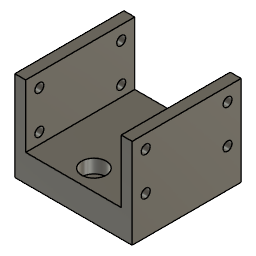
BallCameraHolder_Horizontal_RC2_short_base10mm (Autodesk Fusion 360 design; units mm, degrees)
part number: 2026-10-22-13-06-07-464
Autodesk Fusion 360 part; units mm, degrees
sketch "Sketch2" plane through (0, 0, 0) normal (0, 0, 1) x (1, 0, 0)
  line L0 (-21.5, 20) -> (21.5, 20)
  line L1 (21.5, 20) -> (21.5, -20)
  line L2 (21.5, -20) -> (-21.5, -20)
  line L3 (-21.5, -20) -> (-21.5, 20)
  line L4 (-21.5, 20) -> (21.5, -20) construction
  line L5 (21.5, 20) -> (-21.5, -20) construction
  line L6 (0, -20) -> (0, -12.5) construction
  circle A0 centre (0, -12.5) radius 2
  line L7 (0, 20) -> (0, 12.5) construction
  circle A1 centre (0, 12.5) radius 2
  dimension "d1" = 43
  dimension "d2" = 40
  dimension "d3" = 7.5
  dimension "d4" = 4
  dimension "d5" = 7.5
  dimension "d6" = 4
  constraint horizontal L0
  constraint perpendicular L0 L1
  constraint parallel L0 L2
  constraint parallel L1 L3
  constraint coincident L4 origin
  constraint coincident L5 origin
  constraint midpoint L2 L6.start
  constraint perpendicular L2 L6
  constraint coincident L6.end A0.centre
  constraint midpoint L0 L7.start
  constraint perpendicular L0 L7
  constraint coincident L7.end A1.centre
  measures "d1" distance of L1.end L2.end
  measures "d2" distance of L0.end L1.end
  measures "d3" distance of L6.start L6.end
  measures "d4" diameter of A0
  measures "d5" distance of L7.start L7.end
  measures "d6" diameter of A1
extrude "Extrude1" add sketch "Sketch2" along normal blind 5
sketch "Sketch3" plane through (0, 0, 5) normal (0, 0, 1) x (-1, 0, 0)
  circle A0 centre (0, 12.5) radius 2
  circle A1 centre (0, -12.5) radius 2
  line L0 (21.5, 20) -> (-21.5, 20)
  line L1 (-21.5, 20) -> (-21.5, -20)
  line L2 (-21.5, -20) -> (21.5, -20)
  line L3 (21.5, -20) -> (21.5, 20)
  line L4 (21.5, 20) -> (17.5, 20)
  line L5 (17.5, 20) -> (17.5, -20)
  line L6 (17.5, -20) -> (21.5, -20)
  line L7 (21.5, -20) -> (21.5, 20)
  line L8 (-21.5, -20) -> (-17.5, -20)
  line L9 (-17.5, -20) -> (-17.5, 20)
  line L10 (-17.5, 20) -> (-21.5, 20)
  line L11 (-21.5, 20) -> (-21.5, -20)
  circle A2 centre (0, 12.5) radius 4.5
  circle A3 centre (0, -12.5) radius 4.5
  dimension "d9" = 4
  dimension "d10" = 4
  dimension "d11" = 9
  dimension "d12" = 9
  constraint horizontal L4
  constraint vertical L5
  constraint horizontal L6
  constraint vertical L7
  constraint coincident L0.start L3.end
  constraint horizontal L8
  constraint vertical L9
  constraint horizontal L10
  constraint vertical L11
  constraint coincident L1.end L2.start
  constraint concentric A0 A2
  constraint concentric A1 A3
  measures "d9" distance of L0.start L4.end
  measures "d10" distance of L1.end L8.end
  measures "d11" diameter of A2
  measures "d12" diameter of A3
extrude "Extrude2" add sketch "Sketch3" along normal blind 28 contours L0 L2 L3 L4 L5 L6 L7 | L0 L1 L2 L8 L9 L10 L11
extrude "Extrude3" add sketch "Sketch3" along normal blind 5 contours L0 L2 L5 L9
sketch "Sketch4" plane through (21.5, 0, 0) normal (1, 0, 0) x (0, 1, 0)
  line L0 (20, 0) -> (20, 33)
  line L1 (20, 33) -> (-20, 33)
  line L2 (-20, 33) -> (-20, 0)
  line L3 (-20, 33) -> (-15, 33) construction
  line L4 (-15, 33) -> (-15, 28) construction
  line L5 (-15, 28) -> (-20, 28) construction
  line L6 (-20, 28) -> (-20, 33) construction
  line L7 (20, 33) -> (15, 33) construction
  line L8 (15, 33) -> (15, 28) construction
  line L9 (15, 28) -> (20, 28) construction
  line L10 (20, 28) -> (20, 33) construction
  line L11 (-20, 33) -> (-20, 10) construction
  line L12 (-20, 10) -> (-15, 10) construction
  line L13 (-15, 10) -> (-15, 14) construction
  line L14 (-15, 14) -> (-20, 14) construction
  line L15 (-20, 14) -> (-20, 10) construction
  line L16 (20, 33) -> (20, 10) construction
  line L17 (20, 10) -> (15, 10) construction
  line L18 (15, 10) -> (15, 14) construction
  line L19 (15, 14) -> (20, 14) construction
  line L20 (20, 14) -> (20, 10) construction
  circle A0 centre (-15, 14) radius 1.65
  circle A1 centre (15, 14) radius 1.65
  circle A2 centre (-15, 28) radius 1.65
  circle A3 centre (15, 28) radius 1.65
  dimension "d17" = 5
  dimension "d18" = 5
  dimension "d22" = 5
  dimension "d23" = 5
  dimension "d29" = 23
  dimension "d30" = 5
  dimension "d31" = 4
  dimension "d32" = 23
  dimension "d33" = 5
  dimension "d34" = 4
  dimension "d35" = 3.3
  dimension "d36" = 3.3
  dimension "d37" = 3.3
  dimension "d38" = 3.3
  constraint horizontal L3
  constraint vertical L4
  constraint horizontal L5
  constraint vertical L6
  constraint coincident L1.end L2.start
  constraint horizontal L7
  constraint vertical L8
  constraint horizontal L9
  constraint vertical L10
  constraint coincident L0.end L1.start
  constraint perpendicular L1 L11
  constraint horizontal L12
  constraint vertical L13
  constraint horizontal L14
  constraint vertical L15
  constraint perpendicular L7 L16
  constraint horizontal L17
  constraint vertical L18
  constraint horizontal L19
  constraint vertical L20
  constraint coincident L13.end L14.start
  constraint coincident L18.end L19.start
  constraint coincident L4.end L5.start
  constraint coincident L8.end L9.start
  measures "d17" distance of L1.end L3.end
  measures "d18" distance of L1.end L5.end
  measures "d22" distance of L0.end L7.end
  measures "d23" distance of L0.end L9.end
  measures "d29" distance of L1.end L11.end
  measures "d30" distance of L11.end L12.end
  measures "d31" distance of L11.end L14.end
  measures "d32" distance of L0.end L16.end
  measures "d33" distance of L16.end L17.end
  measures "d34" distance of L16.end L19.end
  measures "d35" diameter of A0
  measures "d36" diameter of A1
  measures "d37" diameter of A2
  measures "d38" diameter of A3
extrude "Extrude4" cut sketch "Sketch4" against normal blind 62
equation "d3 = 5.5 mm + 2 mm"
equation "d5 = 5.5 mm + 2 mm"
equation "d11 = ( 4.5 * 2 ) * 1 mm"
equation "d12 = ( 4.5 * 2 ) * 1 mm"
equation "d13 = 23 mm + 5 mm"
equation "d17 = 3.35 mm + ( 3.3 / 2 ) * 1 mm"
equation "d18 = 3.35 mm + ( 3.3 / 2 ) * 1 mm"
equation "d22 = 3.35 mm + ( 3.3 / 2 ) * 1 mm"
equation "d23 = 3.35 mm + ( 3.3 / 2 ) * 1 mm"
equation "d30 = 3.35 mm + ( 3.3 / 2 ) * 1 mm"
equation "d31 = 2.35 mm + ( 3.3 / 2 ) * 1 mm"
equation "d33 = 3.35 mm + ( 3.3 / 2 ) * 1 mm"
equation "d34 = 2.35 mm + ( 3.3 / 2 ) * 1 mm"
